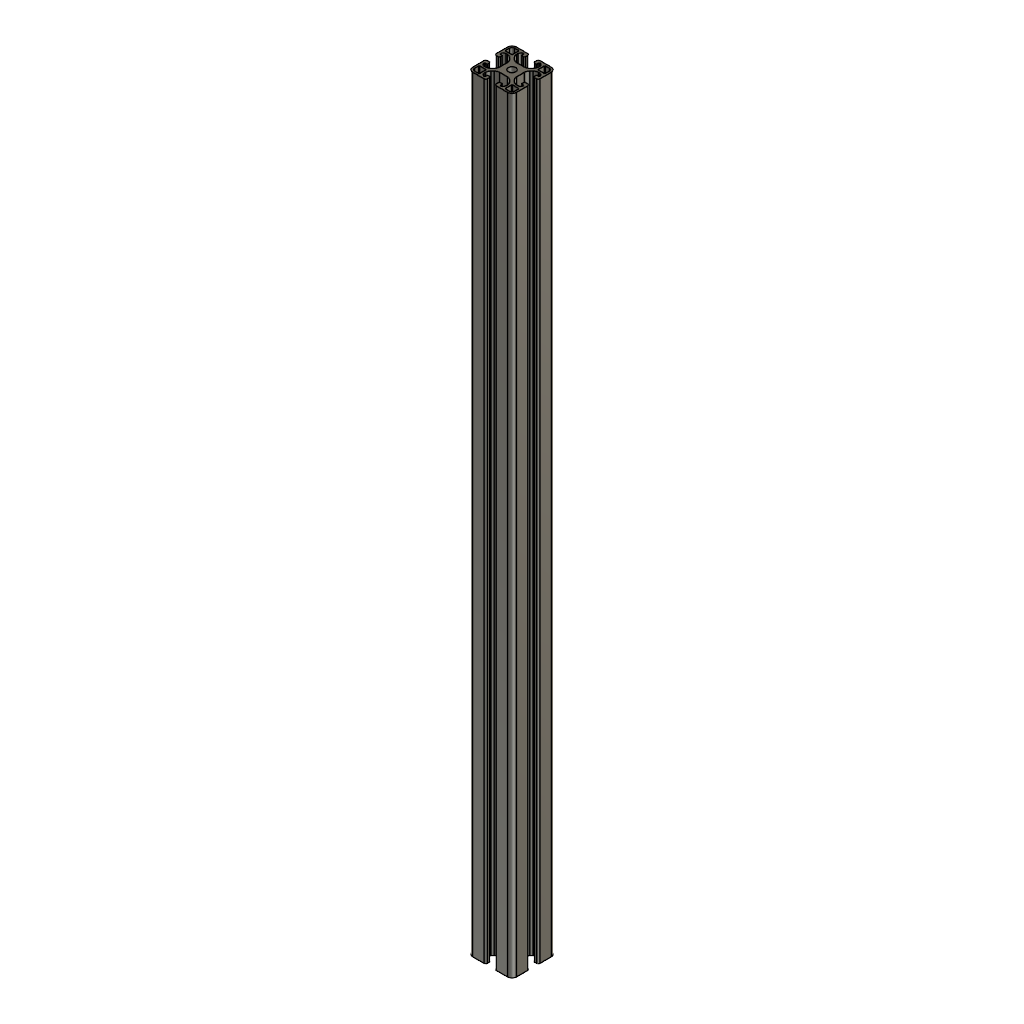
06-03 Alu Profile 40x40 L700 (Autodesk Fusion 360 design; units mm, degrees)
Autodesk Fusion 360 part; units mm, degrees
sketch "Sketch1" plane through (0, 0, 0) normal (0, 0, 1) x (1, 0, 0)
  arc A0 (-18, 7.5) -> (-17.5, 7) centre (-17.5, 7.5) ccw
  arc A1 (-7.75, 3.5576) -> (-9.2145, 7.0931) centre (-12.75, 3.5576) ccw
  arc A2 (-10, 14.1924) -> (-8.5355, 10.6569) centre (-5, 14.1924) ccw
  arc A3 (-16, 18.2) -> (-18.2, 16) centre (-16, 16) ccw
  arc A4 (-15.5, 6.5) -> (-16, 7) centre (-16, 6.5) ccw
  circle A5 centre (0, 0) radius 3.4
  arc A6 (-10.6569, 8.5355) -> (-14.1924, 10) centre (-14.1924, 5) ccw
  line L0 (3.5576, 7.75) -> (-3.5576, 7.75)
  arc A7 (-15.5, 10) -> (-18, 7.5) centre (-15.5, 7.5) ccw
  arc A8 (-20, 5.5) -> (-18.5, 4) centre (-18.5, 5.5) ccw
  line L1 (20, 5.5) -> (20, 16)
  arc A9 (14.1924, 10) -> (10.6569, 8.5355) centre (14.1924, 5) ccw
  line L2 (-5.5, 20) -> (-16, 20)
  arc A10 (-7, 17.5) -> (-7.5, 18) centre (-7.5, 17.5) ccw
  line L3 (-20, 16) -> (-20, 5.5)
  arc A11 (-7.0931, 9.2145) -> (-3.5576, 7.75) centre (-3.5576, 12.75) ccw
  arc A12 (-10, 14.1924) -> (-8.5355, 10.6569) centre (-5, 14.1924) ccw
  arc A13 (-16.5, 4) -> (-15.5, 5) centre (-16.5, 5) ccw
  arc A14 (-7, 16) -> (-6.5, 15.5) centre (-6.5, 16) ccw
  arc A15 (-5, 15.5) -> (-4, 16.5) centre (-5, 16.5) ccw
  line L4 (-3.5576, -7.75) -> (3.5576, -7.75)
  arc A16 (-7.5, 18) -> (-10, 15.5) centre (-7.5, 15.5) ccw
  arc A17 (-4, 18.5) -> (-5.5, 20) centre (-5.5, 18.5) ccw
  line L5 (-7, 17.5) -> (-7, 16)
  arc A18 (-18, 7.5) -> (-17.5, 7) centre (-17.5, 7.5) ccw
  arc A19 (-18.2, 12.3) -> (-17.7, 11.8) centre (-17.7, 12.3) ccw
  arc A20 (-7.75, 3.5576) -> (-9.2145, 7.0931) centre (-12.75, 3.5576) ccw
  line L6 (10.6569, -8.5355) -> (9.2145, -7.0931)
  arc A21 (7.5, 18) -> (7, 17.5) centre (7.5, 17.5) ccw
  line L7 (-4, 16.5) -> (-4, 18.5)
  arc A22 (-11.8, 17.7) -> (-12.3, 18.2) centre (-12.3, 17.7) ccw
  arc A23 (4, 16.5) -> (5, 15.5) centre (5, 16.5) ccw
  line L8 (-16, 18.2) -> (-12.3, 18.2)
  arc A24 (3.5576, 7.75) -> (7.0931, 9.2145) centre (3.5576, 12.75) ccw
  line L9 (-20, 16) -> (-20, 5.5)
  line L10 (-20, -5.5) -> (-20, -16)
  line L11 (-7.0931, 9.2145) -> (-8.5355, 10.6569)
  arc A25 (7.0931, -9.2145) -> (3.5576, -7.75) centre (3.5576, -12.75) ccw
  arc A26 (4, -18.5) -> (5.5, -20) centre (5.5, -18.5) ccw
  arc A27 (5, -15.5) -> (4, -16.5) centre (5, -16.5) ccw
  arc A28 (-16, -7) -> (-15.5, -6.5) centre (-16, -6.5) ccw
  line L12 (-12.3, 11.8) -> (-17.7, 11.8)
  arc A29 (-17.5, -7) -> (-18, -7.5) centre (-17.5, -7.5) ccw
  arc A30 (-18, -7.5) -> (-15.5, -10) centre (-15.5, -7.5) ccw
  arc A31 (-15.5, 6.5) -> (-16, 7) centre (-16, 6.5) ccw
  arc A32 (-18.5, -4) -> (-20, -5.5) centre (-18.5, -5.5) ccw
  line L13 (-6.5, 15.5) -> (-5, 15.5)
  arc A33 (10, -14.1924) -> (8.5355, -10.6569) centre (5, -14.1924) ccw
  line L14 (-10, 14.1924) -> (-10, 15.5)
  line L15 (-10.6569, 8.5355) -> (-9.2145, 7.0931)
  arc A34 (-12.3, 11.8) -> (-11.8, 12.3) centre (-12.3, 12.3) ccw
  arc A35 (-16.5, 4) -> (-15.5, 5) centre (-16.5, 5) ccw
  arc A36 (7.5, -18) -> (10, -15.5) centre (7.5, -15.5) ccw
  arc A37 (10, 15.5) -> (7.5, 18) centre (7.5, 15.5) ccw
  line L16 (-3.5576, -7.75) -> (3.5576, -7.75)
  arc A38 (-5, 15.5) -> (-4, 16.5) centre (-5, 16.5) ccw
  arc A39 (-7, 16) -> (-6.5, 15.5) centre (-6.5, 16) ccw
  line L17 (16, 20) -> (5.5, 20)
  arc A40 (7.75, -3.5576) -> (9.2145, -7.0931) centre (12.75, -3.5576) ccw
  arc A41 (-7, 17.5) -> (-7.5, 18) centre (-7.5, 17.5) ccw
  arc A42 (7, -16) -> (6.5, -15.5) centre (6.5, -16) ccw
  arc A43 (-15.5, 10) -> (-18, 7.5) centre (-15.5, 7.5) ccw
  arc A44 (-15.5, -5) -> (-16.5, -4) centre (-16.5, -5) ccw
  line L18 (-15.5, 10) -> (-14.1924, 10)
  line L19 (-11.8, 17.7) -> (-11.8, 12.3)
  arc A45 (-7.5, 18) -> (-10, 15.5) centre (-7.5, 15.5) ccw
  arc A46 (7, -17.5) -> (7.5, -18) centre (7.5, -17.5) ccw
  arc A47 (6.5, 15.5) -> (7, 16) centre (6.5, 16) ccw
  line L20 (-5.5, 20) -> (-16, 20)
  line L21 (5.5, -20) -> (16, -20)
  arc A48 (-4, 18.5) -> (-5.5, 20) centre (-5.5, 18.5) ccw
  line L22 (-18.2, 12.3) -> (-18.2, 16)
  arc A49 (-7.0931, 9.2145) -> (-3.5576, 7.75) centre (-3.5576, 12.75) ccw
  arc A50 (8.5355, 10.6569) -> (10, 14.1924) centre (5, 14.1924) ccw
  arc A51 (9.2145, 7.0931) -> (7.75, 3.5576) centre (12.75, 3.5576) ccw
  arc A52 (-20, 5.5) -> (-18.5, 4) centre (-18.5, 5.5) ccw
  arc A53 (-17.5, -7) -> (-18, -7.5) centre (-17.5, -7.5) ccw
  line L23 (5.5, -20) -> (16, -20)
  line L24 (4, 18.5) -> (4, 16.5)
  line L25 (14.1924, 10) -> (15.5, 10)
  arc A54 (-10, -15.5) -> (-7.5, -18) centre (-7.5, -15.5) ccw
  line L26 (-11.8, 17.7) -> (-11.8, 12.3)
  arc A55 (10.6569, -8.5355) -> (14.1924, -10) centre (14.1924, -5) ccw
  line L27 (10, 15.5) -> (10, 14.1924)
  arc A56 (-20, -16) -> (-16, -20) centre (-16, -16) ccw
  arc A57 (-18.5, -4) -> (-20, -5.5) centre (-18.5, -5.5) ccw
  arc A58 (-16, 18.2) -> (-18.2, 16) centre (-16, 16) ccw
  arc A59 (-17.7, -11.8) -> (-18.2, -12.3) centre (-17.7, -12.3) ccw
  line L28 (14.1924, 10) -> (15.5, 10)
  arc A60 (15.5, 5) -> (16.5, 4) centre (16.5, 5) ccw
  arc A61 (-18.2, 12.3) -> (-17.7, 11.8) centre (-17.7, 12.3) ccw
  arc A62 (3.5576, 7.75) -> (7.0931, 9.2145) centre (3.5576, 12.75) ccw
  line L29 (-9.2145, -7.0931) -> (-10.6569, -8.5355)
  arc A63 (-11.8, 17.7) -> (-12.3, 18.2) centre (-12.3, 17.7) ccw
  line L30 (-14.1924, -10) -> (-15.5, -10)
  line L31 (18.5, -4) -> (16.5, -4)
  line L32 (-17.7, -11.8) -> (-12.3, -11.8)
  arc A64 (15.5, -10) -> (18, -7.5) centre (15.5, -7.5) ccw
  line L33 (9.2145, 7.0931) -> (10.6569, 8.5355)
  line L34 (16.5, 4) -> (18.5, 4)
  line L35 (-6.5, 15.5) -> (-5, 15.5)
  line L36 (-18.5, 4) -> (-16.5, 4)
  line L37 (-15.5, -6.5) -> (-15.5, -5)
  line L38 (-15.5, 5) -> (-15.5, 6.5)
  line L39 (6.5, -15.5) -> (5, -15.5)
  line L40 (20, -16) -> (20, -5.5)
  line L41 (7.75, -3.5576) -> (7.75, 3.5576)
  line L42 (-16, -20) -> (-5.5, -20)
  line L43 (7, -17.5) -> (7, -16)
  line L44 (-7, 17.5) -> (-7, 16)
  line L45 (-16, 7) -> (-17.5, 7)
  arc A65 (15.5, 5) -> (16.5, 4) centre (16.5, 5) ccw
  line L46 (-17.5, -7) -> (-16, -7)
  arc A66 (-12.3, 11.8) -> (-11.8, 12.3) centre (-12.3, 12.3) ccw
  arc A67 (-18.2, -16) -> (-16, -18.2) centre (-16, -16) ccw
  arc A68 (-18.2, -16) -> (-16, -18.2) centre (-16, -16) ccw
  line L47 (-7.75, 3.5576) -> (-7.75, -3.5576)
  arc A69 (-12.3, -18.2) -> (-11.8, -17.7) centre (-12.3, -17.7) ccw
  arc A70 (-5.5, -20) -> (-4, -18.5) centre (-5.5, -18.5) ccw
  arc A71 (-11.8, -12.3) -> (-12.3, -11.8) centre (-12.3, -12.3) ccw
  line L48 (7.75, -3.5576) -> (7.75, 3.5576)
  line L49 (-9.2145, -7.0931) -> (-10.6569, -8.5355)
  arc A72 (-12.3, -18.2) -> (-11.8, -17.7) centre (-12.3, -17.7) ccw
  arc A73 (-17.7, -11.8) -> (-18.2, -12.3) centre (-17.7, -12.3) ccw
  arc A74 (-7.5, -18) -> (-7, -17.5) centre (-7.5, -17.5) ccw
  line L50 (-18.5, 4) -> (-16.5, 4)
  line L51 (-15.5, -6.5) -> (-15.5, -5)
  arc A75 (16, 7) -> (15.5, 6.5) centre (16, 6.5) ccw
  line L52 (8.5355, 10.6569) -> (7.0931, 9.2145)
  line L53 (-15.5, 5) -> (-15.5, 6.5)
  arc A76 (17.5, 7) -> (18, 7.5) centre (17.5, 7.5) ccw
  line L54 (-10, 14.1924) -> (-10, 15.5)
  line L55 (-14.1924, -10) -> (-15.5, -10)
  arc A77 (18, 7.5) -> (15.5, 10) centre (15.5, 7.5) ccw
  arc A78 (18.5, 4) -> (20, 5.5) centre (18.5, 5.5) ccw
  arc A79 (-18, -7.5) -> (-15.5, -10) centre (-15.5, -7.5) ccw
  line L56 (-5, -15.5) -> (-6.5, -15.5)
  line L57 (10, -14.1924) -> (10, -15.5)
  line L58 (7.0931, -9.2145) -> (8.5355, -10.6569)
  arc A80 (5.5, 20) -> (4, 18.5) centre (5.5, 18.5) ccw
  line L59 (-16, 7) -> (-17.5, 7)
  arc A81 (-10.6569, 8.5355) -> (-14.1924, 10) centre (-14.1924, 5) ccw
  line L60 (3.5576, 7.75) -> (-3.5576, 7.75)
  line L61 (-10.6569, 8.5355) -> (-9.2145, 7.0931)
  line L62 (4, -16.5) -> (4, -18.5)
  line L63 (-4, 16.5) -> (-4, 18.5)
  arc A82 (-16, 20) -> (-20, 16) centre (-16, 16) ccw
  line L64 (-16.5, -4) -> (-18.5, -4)
  line L65 (-15.5, 10) -> (-14.1924, 10)
  line L66 (-7.0931, 9.2145) -> (-8.5355, 10.6569)
  line L67 (9.2145, 7.0931) -> (10.6569, 8.5355)
  line L68 (-7, -16) -> (-7, -17.5)
  arc A83 (7, -17.5) -> (7.5, -18) centre (7.5, -17.5) ccw
  line L69 (-18.2, 12.3) -> (-18.2, 16)
  line L70 (-16, 18.2) -> (-12.3, 18.2)
  line L71 (15.5, -10) -> (14.1924, -10)
  line L72 (17.7, 11.8) -> (12.3, 11.8)
  arc A84 (7.0931, -9.2145) -> (3.5576, -7.75) centre (3.5576, -12.75) ccw
  line L73 (15.5, -10) -> (14.1924, -10)
  arc A85 (18.5, 4) -> (20, 5.5) centre (18.5, 5.5) ccw
  arc A86 (8.5355, 10.6569) -> (10, 14.1924) centre (5, 14.1924) ccw
  line L74 (11.8, 12.3) -> (11.8, 17.7)
  arc A87 (12.3, 18.2) -> (11.8, 17.7) centre (12.3, 17.7) ccw
  arc A88 (20, -5.5) -> (18.5, -4) centre (18.5, -5.5) ccw
  line L75 (-17.7, -11.8) -> (-12.3, -11.8)
  arc A89 (16.5, -4) -> (15.5, -5) centre (16.5, -5) ccw
  arc A90 (6.5, 15.5) -> (7, 16) centre (6.5, 16) ccw
  arc A91 (11.8, 12.3) -> (12.3, 11.8) centre (12.3, 12.3) ccw
  line L76 (18.2, 16) -> (18.2, 12.3)
  arc A92 (4, 16.5) -> (5, 15.5) centre (5, 16.5) ccw
  line L77 (12.3, -11.8) -> (17.7, -11.8)
  line L78 (12.3, -11.8) -> (17.7, -11.8)
  arc A93 (17.5, 7) -> (18, 7.5) centre (17.5, 7.5) ccw
  line L79 (18.2, -12.3) -> (18.2, -16)
  line L80 (-5, -15.5) -> (-6.5, -15.5)
  arc A94 (18.2, -12.3) -> (17.7, -11.8) centre (17.7, -12.3) ccw
  line L81 (16, -7) -> (17.5, -7)
  arc A95 (-14.1924, -10) -> (-10.6569, -8.5355) centre (-14.1924, -5) ccw
  arc A96 (-9.2145, -7.0931) -> (-7.75, -3.5576) centre (-12.75, -3.5576) ccw
  line L82 (-10, -15.5) -> (-10, -14.1924)
  line L83 (11.8, -17.7) -> (11.8, -12.3)
  arc A97 (10, -14.1924) -> (8.5355, -10.6569) centre (5, -14.1924) ccw
  line L84 (18.5, -4) -> (16.5, -4)
  arc A98 (-3.5576, -7.75) -> (-7.0931, -9.2145) centre (-3.5576, -12.75) ccw
  line L85 (4, -16.5) -> (4, -18.5)
  arc A99 (14.1924, 10) -> (10.6569, 8.5355) centre (14.1924, 5) ccw
  line L86 (-8.5355, -10.6569) -> (-7.0931, -9.2145)
  line L87 (-4, -18.5) -> (-4, -16.5)
  line L88 (15.5, -5) -> (15.5, -6.5)
  arc A100 (-5.5, -20) -> (-4, -18.5) centre (-5.5, -18.5) ccw
  line L89 (-12.3, -18.2) -> (-16, -18.2)
  arc A101 (18.2, -12.3) -> (17.7, -11.8) centre (17.7, -12.3) ccw
  line L90 (10.6569, -8.5355) -> (9.2145, -7.0931)
  line L91 (-18.2, -16) -> (-18.2, -12.3)
  line L92 (15.5, -5) -> (15.5, -6.5)
  arc A102 (5.5, 20) -> (4, 18.5) centre (5.5, 18.5) ccw
  arc A103 (16, -20) -> (20, -16) centre (16, -16) ccw
  arc A104 (16, -18.2) -> (18.2, -16) centre (16, -16) ccw
  line L93 (7, -17.5) -> (7, -16)
  line L94 (10, -14.1924) -> (10, -15.5)
  line L95 (-16.5, -4) -> (-18.5, -4)
  arc A105 (7.75, -3.5576) -> (9.2145, -7.0931) centre (12.75, -3.5576) ccw
  line L96 (-12.3, -18.2) -> (-16, -18.2)
  arc A106 (7.5, 18) -> (7, 17.5) centre (7.5, 17.5) ccw
  arc A107 (10.6569, -8.5355) -> (14.1924, -10) centre (14.1924, -5) ccw
  line L97 (-12.3, 11.8) -> (-17.7, 11.8)
  arc A108 (15.5, -6.5) -> (16, -7) centre (16, -6.5) ccw
  arc A109 (20, 16) -> (16, 20) centre (16, 16) ccw
  line L98 (-16, -20) -> (-5.5, -20)
  arc A110 (-4, -16.5) -> (-5, -15.5) centre (-5, -16.5) ccw
  arc A111 (18, 7.5) -> (15.5, 10) centre (15.5, 7.5) ccw
  arc A112 (7.5, -18) -> (10, -15.5) centre (7.5, -15.5) ccw
  line L99 (16, -7) -> (17.5, -7)
  line L100 (17.5, 7) -> (16, 7)
  line L101 (11.8, -17.7) -> (11.8, -12.3)
  line L102 (-11.8, -12.3) -> (-11.8, -17.7)
  arc A113 (-9.2145, -7.0931) -> (-7.75, -3.5576) centre (-12.75, -3.5576) ccw
  line L103 (-17.5, -7) -> (-16, -7)
  line L104 (16, 20) -> (5.5, 20)
  line L105 (-4, -18.5) -> (-4, -16.5)
  line L106 (18.2, 16) -> (18.2, 12.3)
  arc A114 (-3.5576, -7.75) -> (-7.0931, -9.2145) centre (-3.5576, -12.75) ccw
  arc A115 (12.3, -11.8) -> (11.8, -12.3) centre (12.3, -12.3) ccw
  line L107 (16.5, 4) -> (18.5, 4)
  arc A116 (4, -18.5) -> (5.5, -20) centre (5.5, -18.5) ccw
  arc A117 (15.5, -10) -> (18, -7.5) centre (15.5, -7.5) ccw
  line L108 (20, -16) -> (20, -5.5)
  arc A118 (17.7, 11.8) -> (18.2, 12.3) centre (17.7, 12.3) ccw
  line L109 (7.0931, -9.2145) -> (8.5355, -10.6569)
  arc A119 (9.2145, 7.0931) -> (7.75, 3.5576) centre (12.75, 3.5576) ccw
  line L110 (4, 18.5) -> (4, 16.5)
  line L111 (15.5, 6.5) -> (15.5, 5)
  arc A120 (5, -15.5) -> (4, -16.5) centre (5, -16.5) ccw
  arc A121 (-14.1924, -10) -> (-10.6569, -8.5355) centre (-14.1924, -5) ccw
  line L112 (5, 15.5) -> (6.5, 15.5)
  arc A122 (16, 7) -> (15.5, 6.5) centre (16, 6.5) ccw
  line L113 (6.5, -15.5) -> (5, -15.5)
  line L114 (-20, -5.5) -> (-20, -16)
  arc A123 (-15.5, -5) -> (-16.5, -4) centre (-16.5, -5) ccw
  line L115 (7, 16) -> (7, 17.5)
  line L116 (-7.75, 3.5576) -> (-7.75, -3.5576)
  arc A124 (16.5, -4) -> (15.5, -5) centre (16.5, -5) ccw
  arc A125 (18, -7.5) -> (17.5, -7) centre (17.5, -7.5) ccw
  arc A126 (11.8, 12.3) -> (12.3, 11.8) centre (12.3, 12.3) ccw
  line L117 (15.5, 6.5) -> (15.5, 5)
  line L118 (20, 5.5) -> (20, 16)
  arc A127 (-16, 20) -> (-20, 16) centre (-16, 16) ccw
  arc A128 (-6.5, -15.5) -> (-7, -16) centre (-6.5, -16) ccw
  arc A129 (18.2, 16) -> (16, 18.2) centre (16, 16) ccw
  line L119 (10, 15.5) -> (10, 14.1924)
  arc A130 (18.2, 16) -> (16, 18.2) centre (16, 16) ccw
  line L120 (-11.8, -12.3) -> (-11.8, -17.7)
  arc A131 (12.3, -11.8) -> (11.8, -12.3) centre (12.3, -12.3) ccw
  line L121 (11.8, 12.3) -> (11.8, 17.7)
  arc A132 (15.5, -6.5) -> (16, -7) centre (16, -6.5) ccw
  arc A133 (16, -18.2) -> (18.2, -16) centre (16, -16) ccw
  line L122 (12.3, 18.2) -> (16, 18.2)
  line L123 (5, 15.5) -> (6.5, 15.5)
  arc A134 (12.3, 18.2) -> (11.8, 17.7) centre (12.3, 17.7) ccw
  arc A135 (-8.5355, -10.6569) -> (-10, -14.1924) centre (-5, -14.1924) ccw
  arc A136 (-7.5, -18) -> (-7, -17.5) centre (-7.5, -17.5) ccw
  line L124 (-10, -15.5) -> (-10, -14.1924)
  arc A137 (16, -20) -> (20, -16) centre (16, -16) ccw
  line L125 (17.5, 7) -> (16, 7)
  arc A138 (-16, -7) -> (-15.5, -6.5) centre (-16, -6.5) ccw
  arc A139 (-11.8, -12.3) -> (-12.3, -11.8) centre (-12.3, -12.3) ccw
  arc A140 (-10, -15.5) -> (-7.5, -18) centre (-7.5, -15.5) ccw
  line L126 (-18.2, -16) -> (-18.2, -12.3)
  arc A141 (17.7, 11.8) -> (18.2, 12.3) centre (17.7, 12.3) ccw
  line L127 (7, 16) -> (7, 17.5)
  arc A142 (7, -16) -> (6.5, -15.5) centre (6.5, -16) ccw
  line L128 (-8.5355, -10.6569) -> (-7.0931, -9.2145)
  line L129 (12.3, 18.2) -> (16, 18.2)
  line L130 (17.7, 11.8) -> (12.3, 11.8)
  arc A143 (-8.5355, -10.6569) -> (-10, -14.1924) centre (-5, -14.1924) ccw
  line L131 (18.2, -12.3) -> (18.2, -16)
  line L132 (-7, -16) -> (-7, -17.5)
  line L133 (16, -18.2) -> (12.3, -18.2)
  arc A144 (11.8, -17.7) -> (12.3, -18.2) centre (12.3, -17.7) ccw
  arc A145 (11.8, -17.7) -> (12.3, -18.2) centre (12.3, -17.7) ccw
  line L134 (8.5355, 10.6569) -> (7.0931, 9.2145)
  arc A146 (20, 16) -> (16, 20) centre (16, 16) ccw
  arc A147 (-6.5, -15.5) -> (-7, -16) centre (-6.5, -16) ccw
  arc A148 (20, -5.5) -> (18.5, -4) centre (18.5, -5.5) ccw
  line L135 (16, -18.2) -> (12.3, -18.2)
  arc A149 (-20, -16) -> (-16, -20) centre (-16, -16) ccw
  arc A150 (18, -7.5) -> (17.5, -7) centre (17.5, -7.5) ccw
  arc A151 (10, 15.5) -> (7.5, 18) centre (7.5, 15.5) ccw
  arc A152 (-4, -16.5) -> (-5, -15.5) centre (-5, -16.5) ccw
  dimension "d1" = 0
  dimension "d2" = 0
  dimension "d3" = 0
  dimension "d4" = 0
  dimension "d5" = 0
  measures "d2" distance of L74
  measures "d3" distance of L26
  measures "d4" distance of L102
  measures "d5" distance of L101
extrude "Extrude1" add sketch "Sketch1" along normal blind 700
